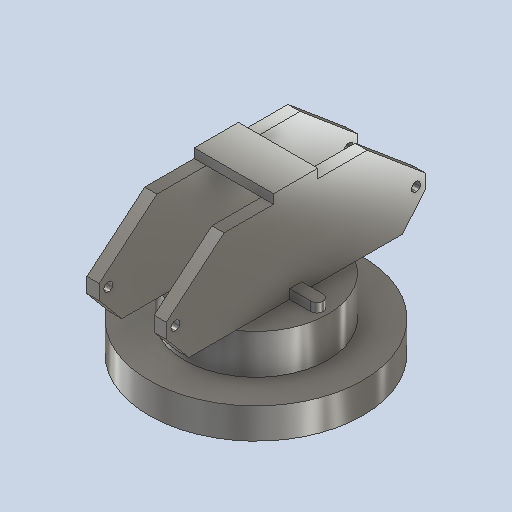
# Autodesk Inventor part: 7
Saved by Autodesk Inventor 2027.1 (Build 311270010, 270A)
## iProperties
Part Number: 7
Material: Allgemein
Document SubType Name: Modellieren
Designer: Asus
Appearance: Chrom - poliert
Author: Asus
Autodesk Inventor part; units mm, degrees
ref_plane "XZ-Ebene" through (0, 0, 0) normal (0, 1, 0) x (-1, 0, 0)
ref_plane "XY-Ebene" through (0, 0, 0) normal (0, 0, 1) x (1, 0, 0)
sketch "Skizze1" plane through (0, 0, 0) normal (0, 0, 1) x (1, 0, 0)
  circle A0 centre (0, 0) radius 35
  dimension "d0" = 70
  constraints: 1 centre point, 1 coincident
  measures "d0" diameter of A0
extrude "Extrusion1" add sketch "Skizze1" along normal blind 10
sketch "Skizze2" plane through (0, 0, 10) normal (0, 0, 1) x (1, 0, 0)
  circle A0 centre (0, 0) radius 23.5
  dimension "d3" = 47
  constraints: 1 centre point, 1 coincident
  measures "d3" diameter of A0
extrude "Extrusion2" add sketch "Skizze2" along normal blind 13
ref_plane "Arbeitsebene1" through (13, 0, 0) normal (1, 0, 0) x (0, 1, 0)
sketch "Skizze3" plane through (13, 0, 0) normal (1, 0, 0) x (0, 1, 0)
  line L0 (-32.4962, 0) -> (-32.4962, 10) construction
  line L1 (-32.4962, 10) -> (-19.5768, 10) construction
  line L2 (-19.5768, 10) -> (-19.5768, 23) construction
  line L3 (-19.5768, 23) -> (19.5768, 23) construction
  line L4 (19.5768, 23) -> (19.5768, 10) construction
  line L5 (19.5768, 10) -> (32.4962, 10) construction
  line L6 (32.4962, 10) -> (32.4962, 0) construction
  line L7 (32.4962, 0) -> (-32.4962, 0) construction
  line L8 (0, 27.6) -> (0, -4.6) construction
  line L9 (-35, 23) -> (35, 23)
  line L10 (-23.45, 52.6) -> (23.45, 52.6)
  line L11 (35, 23) -> (42.3921, 31.8095)
  line L12 (42.3921, 31.8095) -> (42.3921, 36.7057)
  line L13 (42.3921, 36.7057) -> (23.45, 52.6)
  line L14 (0, 52.6) -> (0, 23) construction
  line L15 (-35, 23) -> (-42.3921, 31.8095)
  line L16 (-42.3921, 31.8095) -> (-42.3921, 36.7057)
  line L17 (-42.3921, 36.7057) -> (-23.45, 52.6)
  point P0 (0, 0)
  dimension "d7" = 70
  dimension "d8" = 46.9
  dimension "d9" = 29.6
  dimension "d10" = 11.5
  dimension "d11" = 50
  dimension "d13" = 130
  constraints: 18 end point, 3 midpoint, 2 symmetric about line, 1 collinear, 1 horizontal, 1 perpendicular, 1 vertical, 1 vertical alignment
  measures "d7" distance of L9.start L9.end
  measures "d8" distance of L10.start L10.end
  measures "d9" distance between parallel lines of L3 L10
  measures "d10" distance of L9.end L11.end
  measures "d11" angle of L13 L12
  measures "d13" angle of L9 L11
extrude "Extrusion3" add sketch "Skizze3" against normal blind 4
sketch "Skizze4" plane through (13, 0, 0) normal (1, 0, 0) x (0, 0, -1)
  line L0 (0, -32.4962) -> (-10, -32.4962) construction
  line L1 (-10, -32.4962) -> (-10, -19.5768) construction
  line L2 (-10, -19.5768) -> (-23, -19.5768) construction
  line L3 (-23, 19.5768) -> (-23, -19.5768) construction
  line L4 (-23, 35) -> (-23, 19.5768) construction
  line L5 (-31.8095, 42.3921) -> (-23, 35) construction
  line L6 (-36.7057, 42.3921) -> (-31.8095, 42.3921) construction
  line L7 (-52.6, 23.45) -> (-36.7057, 42.3921) construction
  line L8 (-52.6, -23.45) -> (-52.6, 23.45) construction
  line L9 (-36.7057, -42.3921) -> (-52.6, -23.45) construction
  line L10 (-31.8095, -42.3921) -> (-36.7057, -42.3921) construction
  line L11 (-23, -35) -> (-31.8095, -42.3921) construction
  line L12 (-23, -19.5768) -> (-23, -35) construction
  line L13 (0, 32.4962) -> (0, -32.4962) construction
  line L14 (-10, 32.4962) -> (0, 32.4962) construction
  line L15 (-10, 19.5768) -> (-10, 32.4962) construction
  line L16 (-23, 19.5768) -> (-10, 19.5768) construction
  circle A0 centre (-34.2576, -39.3921) radius 1.5
  circle A1 centre (-34.2576, 39.3921) radius 1.5
  point P0 (0, 0)
  point P1 (-34.2576, 42.3921)
  point P2 (-34.2576, -42.3921)
  dimension "d16" = 3
  dimension "d17" = 3
  dimension "d18" = 3
  dimension "d19" = 3
  constraints: 2 centre point, 2 midpoint, 2 vertical alignment
  measures "d16" diameter of A0
  measures "d17" diameter of A1
  measures "d18" distance from line of L6 A1.centre
  measures "d19" distance from line of L10 A0.centre
extrude "Extrusion4" cut sketch "Skizze4" against normal blind 4
mirror "Spiegeln1" about plane through (0, 0, 0) normal (1, 0, 0) of "Extrusion3", "Extrusion4"
sketch "Skizze5" plane through (0, 0, 23) normal (0, 0, 1) x (1, 0, 0)
  line L0 (9, 35) -> (13, 35) construction
  line L1 (13, 35) -> (13, 19.5768) construction
  arc A0 (13, 19.5768) -> (9, 21.7083) centre (0, 0) ccw construction
  arc A1 (9, 21.7083) -> (-9, 21.7083) centre (0, 0) ccw construction
  line L2 (-9, 35) -> (-9, 21.7083) construction
  line L3 (-13, 35) -> (-9, 35) construction
  line L4 (-13, 19.5768) -> (-13, 35) construction
  line L5 (-13, -19.5768) -> (-13, 19.5768) construction
  arc A2 (-13, 19.5768) -> (-13, -19.5768) centre (0, 0) ccw construction
  arc A3 (-9, 21.7083) -> (-13, 19.5768) centre (0, 0) ccw construction
  line L6 (-9, 21.7083) -> (-9, -21.7083) construction
  line L7 (-9, -21.7083) -> (-9, -35) construction
  line L8 (-9, -35) -> (-13, -35) construction
  line L9 (-13, -35) -> (-13, -19.5768) construction
  arc A4 (-13, -19.5768) -> (-9, -21.7083) centre (0, 0) ccw construction
  line L10 (9, 21.7083) -> (9, 35) construction
  line L11 (9, 21.7083) -> (9, -21.7083) construction
  line L12 (9, -35) -> (9, -21.7083) construction
  line L13 (13, -35) -> (9, -35) construction
  line L14 (13, -19.5768) -> (13, -35) construction
  arc A5 (9, -21.7083) -> (13, -19.5768) centre (0, 0) ccw construction
  line L15 (13, 19.5768) -> (13, -19.5768) construction
  arc A6 (13, -19.5768) -> (13, 19.5768) centre (0, 0) ccw construction
  arc A7 (-9, -21.7083) -> (9, -21.7083) centre (0, 0) ccw construction
  line L16 (-49, 0) -> (49, 0) construction
  line L17 (13, -2) -> (22, -2)
  line L18 (22, -2) -> (22, 2)
  line L19 (22, 2) -> (13, 2)
  line L20 (13, 2) -> (13, -2)
  line L21 (13, 23.45) -> (13, -23.45) projected
  line L22 (13, 23.45) -> (13, -23.45) projected
  line L23 (13, 23.45) -> (9, 23.45) projected
  line L24 (9, -23.45) -> (9, 23.45) projected
  line L25 (13, -23.45) -> (9, -23.45) projected
  point P0 (13, 0)
  point P1 (13, 0)
  dimension "d22" = 9
  dimension "d23" = 4
  constraints: 8 end point, 3 midpoint, 2 parallel, 1 coincident, 1 horizontal, 1 perpendicular
  measures "d22" distance of L19.end L18.end
  measures "d23" distance of L18.end L17.end
extrude "Extrusion5" add sketch "Skizze5" along normal blind 3 contours L20 L19 L18 L17
fillet "Rundung1" radius 2 2 edges at (22, -2, 24.5) (22, 2, 24.5)
mirror "Spiegeln2" about plane through (0, 0, 0) normal (1, 0, 0) of "Extrusion5", "Rundung1"
sketch "Skizze6" plane through (-13, -23.45, 52.6) normal (0, 0, 1) x (1, 0, 0)
  line L0 (0, 46.9) -> (0, 0) projected
  line L1 (0, 21.45) -> (-7, 21.45) projected
  arc A0 (-7, 25.45) -> (-7, 21.45) centre (-7, 23.45) ccw projected
  line L2 (-7, 25.45) -> (0, 25.45) projected
  arc A1 (33, 21.45) -> (33, 25.45) centre (33, 23.45) ccw projected
  line L3 (33, 25.45) -> (26, 25.45) projected
  line L4 (26, 21.45) -> (26, 25.45) projected
  line L5 (26, 21.45) -> (33, 21.45) projected
  line L6 (26, 46.9) -> (26, 0) projected
  line L7 (26, 16.2) -> (0, 16.2)
  line L8 (0, 16.2) -> (0, 30.7)
  line L9 (0, 30.7) -> (26, 30.7)
  line L10 (26, 30.7) -> (26, 16.2)
  line L11 (26, 16.2) -> (0, 30.7) construction
  line L12 (0, 16.2) -> (26, 30.7) construction
  point P0 (13, 23.45)
  dimension "d27" = 14.5
  constraints: 12 end point, 2 midpoint, 2 parallel, 1 horizontal, 1 perpendicular, 1 point on line
  measures "d27" distance between parallel lines of L7 L9
extrude "Extrusion6" add sketch "Skizze6" along normal blind 3 contours L9 L6 L4 L7 L0
sketch "Skizze7" plane through (0, 0, 0) normal (0, 0, -1) x (-1, 0, 0)
  circle A0 centre (0, 0) radius 35 projected
  constraints: 1 coincident
hole "Bohrung1" at (0, 0, 0) direction (0, 0, 1) diameter 20 depth 10
equation "\"d18\" = d17"
equation "\"d19\" = d16"
